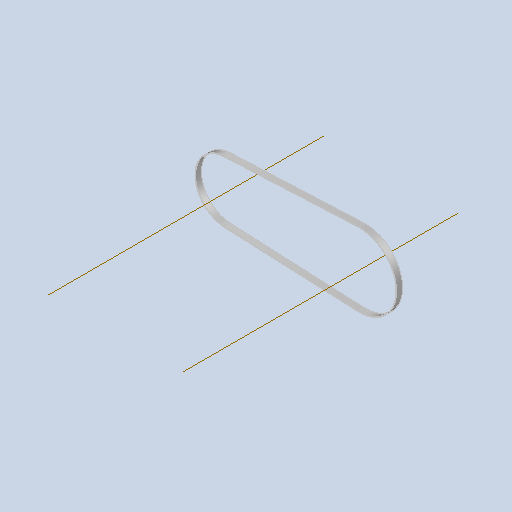
# Autodesk Inventor part: 歯付きベルト
Saved by Autodesk Inventor 2025.3 (Build 293356030, 356C)
## iProperties
Created: 2026-02-24
Part Number: 歯付きベルト
Material: Rubber
Document SubType Name: Modeling
Designer: ibuki_ono
Density: 1 g/cm^3
Appearance: Rubber - Black - Version 1.1
CustomPartVersion: 1
Author: ibuki_ono
Autodesk Inventor part; units mm, degrees
sketch "スケッチ パス" plane through (0, 0, 0) normal (0, 0, 1) x (1, 0, 0)
  arc A0 (-101.4721, 32.3068) -> (-101.4721, -32.3068) centre (-100, 0) ccw
  arc A1 (40.3262, -38.7681) -> (40.3262, 38.7681) centre (42.0928, 0) ccw
  line L0 (40.3262, -38.7681) -> (-101.4721, -32.3068)
  line L1 (-101.4721, 32.3068) -> (40.3262, 38.7681)
  constraints: 4 end point, 4 point on circle, 2 centre point
ref_plane "断面平面" through (-101.4721, -32.3068, 0) normal (0.999, -0.0455, 0) x (0, 0, 1)
ref_plane "作業平面2" through (-100, 0, 0) normal (-1, 0, 0) x (0, 0, 1)
ref_plane "作業平面3" through (42.0928, 0, 0) normal (-1, 0, 0) x (0, 0, 1)
sketch "断面" plane through (-101.4721, -32.3068, 0) normal (0.999, -0.0455, 0) x (0, 0, 1)
  line L0 (-3.175, 0.381) -> (3.175, 0.381)
  line L1 (3.175, 0.381) -> (3.175, -0.254)
  line L2 (3.175, -0.254) -> (-3.175, -0.254)
  line L3 (-3.175, -0.254) -> (-3.175, 0.381)
  line L4 (-3.175, 0) -> (3.175, 0) construction
  point P0 (0, 0)
  point P1 (0, 0)
  dimension "d0" = 6.35
  dimension "d4" = 0.254
  dimension "d5" = 0.381
  constraints: 10 end point, 2 parallel, 2 point on line, 1 coincident, 1 horizontal, 1 midpoint, 1 perpendicular, 1 other
  measures "d0" distance between parallel lines of L1 L3
  measures "d4" distance between parallel lines of L2 L4
  measures "d5" distance between parallel lines of L4 L0
sweep "ベルト" add profiles "断面" path "スケッチ パス"
equation "\"d0\" = da_B"
equation "\"d4\" = da_a"
equation "\"d5\" = da_a2"
equation "\"da_B\" = 6.35"
equation "\"da_pb\" = 2.032"
equation "\"da_L\" = 508"
equation "\"da_a\" = 0.254"
equation "\"da_S\" = 1.143"
equation "\"da_Beta\" = 20deg"
equation "\"da_Ht\" = 0.508"
equation "\"da_H\" = 1.143"
equation "\"da_a2\" = 0.381"
body "Solid1"
